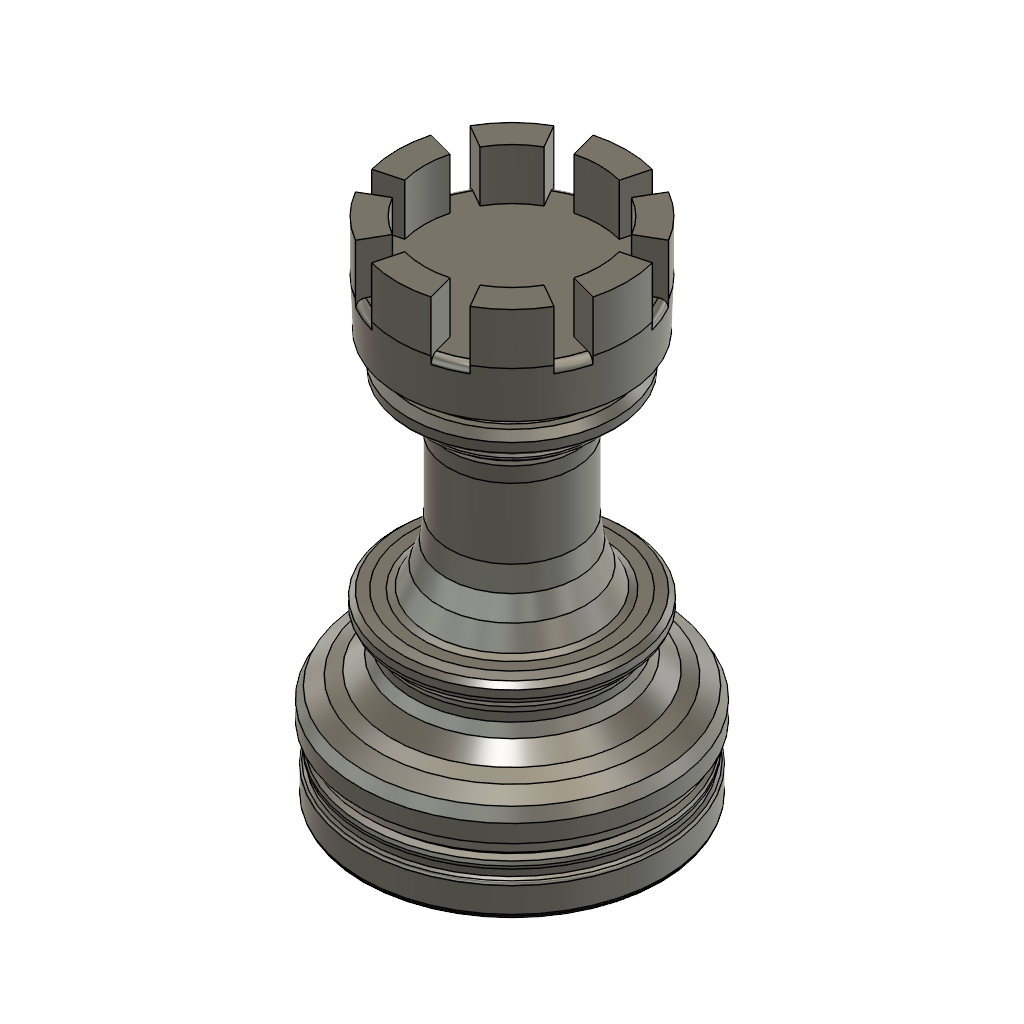
Tower (Autodesk Fusion 360 design; units mm, degrees)
part number: 2026-10-13-14-45-00-244
Autodesk Fusion 360 part; units mm, degrees
sketch "Sketch1" plane through (0, 0, 0) normal (0, 0, 1) x (1, 0, 0)
  line L0 (0, -18.1) -> (2.1, -18.1)
  line L1 (2.1, -18.1) -> (5.6, -17.9)
  line L2 (5.6, -17.9) -> (8.5, -17.4)
  line L3 (8.5, -17.4) -> (10.2, -16.7)
  line L4 (10.2, -16.7) -> (10.3, -16.5)
  line L5 (10.3, -16.5) -> (10.3, -14.6)
  line L6 (10.3, -14.6) -> (10, -14.4)
  line L7 (10, -14.4) -> (10.15, -13.7818)
  line L8 (10.15, -13.7818) -> (10.075, -13.4284)
  line L9 (10.075, -13.4284) -> (9.6033, -13.3139)
  line L10 (9.6033, -13.3139) -> (9.9799, -12.9804)
  line L11 (9.9799, -12.9804) -> (10.5, -12.1)
  line L12 (10.5, -12.1) -> (10.5, -10.9)
  line L13 (10.5, -10.9) -> (10.1125, -10.1526)
  line L14 (10.1125, -10.1526) -> (9.1034, -9.5566)
  line L15 (9.1034, -9.5566) -> (8.2, -9.2)
  line L16 (8.2, -9.2) -> (7.6575, -8.7025)
  line L17 (7.6575, -8.7025) -> (7.1474, -8.2346)
  line L18 (7.1474, -8.2346) -> (6.8, -7.5)
  line L19 (6.8, -7.5) -> (6.8, -6.9)
  line L20 (6.8, -6.9) -> (7.1474, -6.3425)
  line L21 (7.1474, -6.3425) -> (7.8026, -5.6281)
  line L22 (7.8026, -5.6281) -> (7.9288, -5.3339)
  line L23 (7.9288, -5.3339) -> (7.9288, -4.8)
  line L24 (7.9288, -4.8) -> (7.5936, -4.4926)
  line L25 (7.5936, -4.4926) -> (6.9, -4.4)
  line L26 (6.9, -4.4) -> (6.1, -4.4)
  line L27 (6.1, -4.4) -> (5.6617, -4.2347)
  line L28 (5.6617, -4.2347) -> (5, -2.9)
  line L29 (5, -2.9) -> (4.5, -1.5)
  line L30 (4.5, -1.5) -> (4.3, 0.1)
  line L31 (4.3, 0.1) -> (4.3, 2.7)
  line L32 (4.3, 2.7) -> (4.3, 4.9)
  line L33 (4.3, 4.9) -> (4.4, 6)
  line L34 (4.4, 6) -> (5.1, 6.8)
  line L35 (5.1, 6.8) -> (5.6, 7.2)
  line L36 (5.6, 7.2) -> (5.4101, 7.4374)
  line L37 (5.4101, 7.4374) -> (5.4101, 7.8)
  line L38 (5.4101, 7.8) -> (6.4, 8.4)
  line L39 (6.4, 8.4) -> (7, 8.4)
  line L40 (7, 8.4) -> (7.1, 9.3)
  line L41 (7.1, 9.3) -> (6.7, 9.8)
  line L42 (0, 9.9896) -> (0, -18.1)
  line L43 (6.7, 9.8) -> (6.2466, 9.8)
  line L44 (6.2466, 9.8) -> (7.5109, 10.8114)
  line L45 (7.5109, 10.8114) -> (7.7356, 10.9912)
  line L46 (7.7356, 10.9912) -> (7.8539, 14.2278)
  line L47 (7.8539, 14.2278) -> (0, 14.2278)
  line L48 (0, 14.2278) -> (0, 9.9896)
  constraint horizontal L0
  constraint vertical L5
  constraint perpendicular L7 L9
  constraint vertical L12
  constraint perpendicular L11 L14
  constraint parallel L16 L17
  constraint vertical L19
  constraint perpendicular L16 L21
  constraint parallel L19 L23
  constraint perpendicular L21 L24
  constraint perpendicular L23 L26
  constraint vertical L31
  constraint parallel L31 L32
  constraint vertical L37
  constraint horizontal L39
  constraint perpendicular L0 L42
  constraint horizontal L43
  constraint perpendicular L41 L44
  constraint perpendicular L41 L45
  constraint horizontal L47
  constraint perpendicular L47 L48
revolve "Revolve1" add sketch "Sketch1" angle 360 about axis through (0, 9.9896, 0) along (0, -1, 0)
sketch "Sketch2" plane through (0, 14.2278, 0) normal (0, 1, 0) x (-1, 0, 0)
  circle A0 centre (0, 0) radius 7.8539
  circle A1 centre (0, 0) radius 6
  line L0 (0, 0) -> (-2.0327, -7.5863)
  line L1 (0, 0) -> (2.0327, -7.5863)
  line L2 (0, 0) -> (0, -5.5)
  line L3 (0, -5.5) -> (0, -6)
  line L4 (0, 0) -> (3.927, -6.8017)
  line L5 (0, 0) -> (6.8017, -3.927)
  line L6 (0, 0) -> (7.5863, -2.0327)
  line L7 (0, 0) -> (7.5863, 2.0327)
  line L8 (0, 0) -> (6.8017, 3.927)
  line L9 (0, 0) -> (3.927, 6.8017)
  line L10 (0, 0) -> (2.0327, 7.5863)
  line L11 (0, 0) -> (-2.0327, 7.5863)
  line L12 (0, 0) -> (-3.927, 6.8017)
  line L13 (0, 0) -> (-6.8017, 3.927)
  line L14 (0, 0) -> (-7.5863, 2.0327)
  line L15 (0, 0) -> (-7.5863, -2.0327)
  line L16 (0, 0) -> (-6.8017, -3.927)
  line L17 (0, 0) -> (-3.927, -6.8017)
  dimension "d2" = 12
  dimension "d4" = 15
  dimension "d5" = 15
  dimension "d7" = 360
  constraint concentric A0 A1
  constraint coincident A0.centre A1.centre
  constraint coincident A0 L0.end
  constraint coincident A0 L1.end
  constraint vertical L2
  constraint coincident A1 L3.end
  constraint perpendicular A1 L3
  measures "d2" diameter of A1
  measures "d4" angle of L0 L3
  measures "d5" angle of L1 L2
extrude "Extrude1" add sketch "Sketch2" along normal blind 3.5 contours A0 A1 L6 L7 | A0 A1 L8 L9 | A0 A1 L4 L5 | A0 A1 L10 L11 | A0 A1 L0 L1 | A0 A1 L12 L13 | A0 A1 L14 L15 | A0 A1 L16 L17
fillet "Fillet1" radius 0.5 tangency weight 0.99014 8 edges at (-3.0056, 14.2278, 7.2561) (-7.2561, 14.2278, 3.0056) (-7.2561, 14.2278, -3.0056) (-3.0056, 14.2278, -7.2561) (3.0056, 14.2278, -7.2561) (7.2561, 14.2278, -3.0056) (7.2561, 14.2278, 3.0056) (3.0056, 14.2278, 7.2561)
fillet "Fillet2" radius 0.1 1 edges at (-5.221, 7.2, -2.025)
fillet "Fillet3" radius 0.25 1 edges at (-6.5263, 8.4, -2.5313)
fillet "Fillet4" radius 0.25 2 edges at (-9.603, -16.5, -3.7246) (-9.603, -14.6, -3.7246)
fillet "Fillet5" radius 0.4 1 edges at (-9.4631, -13.7818, -3.6704)
sketch "Sketch3" plane through (0, 0, 0) normal (0, 0, 1) x (1, 0, 0)
  line L0 (-8.5, -17.4) -> (9.5169, -17.4)
  line L1 (9.5169, -17.4) -> (9.5169, -18.8567)
  line L2 (9.5169, -18.8567) -> (-8.5, -18.8567)
  line L3 (-8.5, -18.8567) -> (-8.5, -17.4)
  constraint horizontal L0
  constraint vertical L1
  constraint horizontal L2
  constraint vertical L3
extrude "Extrude2" cut sketch "Sketch3" along normal blind 19 and the other way blind 40.5
scale "Scale1" factors (1.1, 1.1, 1.1) about (4.3, 0.1, 0) bodies 1
sketch "Sketch4" plane through (0, -19.15, 0) normal (0, -1, 0) x (1, 0, 0)
  circle A0 centre (-0.43, 0) radius 9.35
  circle A1 centre (-0.43, 0) radius 3.15
  dimension "d27" = 6.3
  constraint concentric A0 A1
  measures "d27" diameter of A1
extrude "Extrude3" cut sketch "Sketch4" against normal blind 2.2 contours A1
